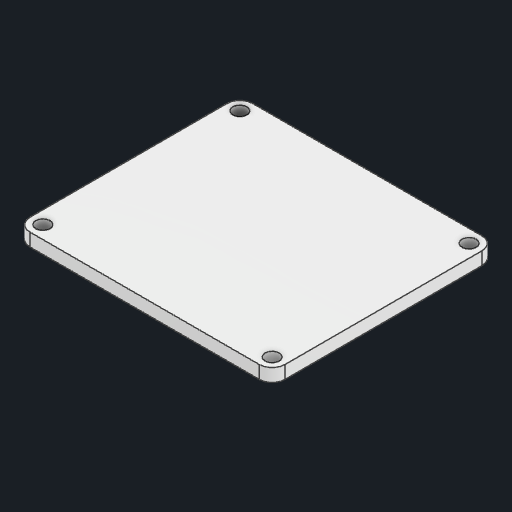
# Autodesk Inventor part: D1 COVER
Saved by Autodesk Inventor 2027.1 (Build 311270010, 270A)
## iProperties
Created: 2026-09-25
Part Number: D1 COVER
Material: ABS 플라스틱
Document SubType Name: Modeling
Designer: work
Density: 1.06 g/cm^3
Appearance: 매끄러움 - 흰색
Author: work
Autodesk Inventor part; units mm, degrees
ref_plane "YZ Plane" through (0, 0, 0) normal (1, 0, 0) x (0, 1, 0)
ref_plane "XZ Plane" through (0, 0, 0) normal (0, 1, 0) x (-1, 0, 0)
ref_plane "XY Plane" through (0, 0, 0) normal (0, 0, 1) x (1, 0, 0)
sketch "스케치1" plane through (0, 0, 0) normal (0, 1, 0) x (-1, 0, 0)
  line L0 (0, 0) -> (35.5, 0)
  line L1 (35.5, 0) -> (35.5, -26.5)
  line L2 (35.5, -26.5) -> (0, -26.5)
  line L3 (0, -26.5) -> (0, 0)
  line L4 (37.5, -28.5) -> (37.5, 2)
  line L5 (37.5, 2) -> (-2, 2) construction
  line L6 (-2, 2) -> (-2, -28.5)
  line L7 (-2, -28.5) -> (37.5, -28.5) construction
  circle A0 centre (35.5, 2) radius 1.1
  circle A1 centre (35.5, 2) radius 2
  circle A2 centre (0, 2) radius 1.1
  circle A3 centre (0, 2) radius 2
  line L8 (0, 4) -> (35.5, 4)
  line L9 (-2, -13.25) -> (37.5, -13.25) construction
  line L10 (0, -26.5) -> (35.5, -26.5)
  line L11 (35.5, -26.5) -> (35.5, 0)
  line L12 (0, 0) -> (0, -26.5)
  line L13 (37.5, 2) -> (37.5, -28.5)
  line L14 (37.5, -28.5) -> (-2, -28.5) construction
  line L15 (-2, -28.5) -> (-2, 2)
  circle A4 centre (35.5, -28.5) radius 1.1
  circle A5 centre (35.5, -28.5) radius 2
  circle A6 centre (0, -28.5) radius 1.1
  circle A7 centre (0, -28.5) radius 2
  line L16 (0, -30.5) -> (35.5, -30.5)
  line L17 (0, -8.25) -> (-2, -8.25)
  line L18 (-2, -8.25) -> (-2, -18.25)
  line L19 (-2, -18.25) -> (0, -18.25)
  line L20 (0, -18.25) -> (0, -8.25)
  line L21 (-2, -6.25) -> (-1, -6.25)
  line L22 (-1, -6.25) -> (-1, -20.25)
  line L23 (-1, -20.25) -> (-2, -20.25)
  line L24 (-2, -20.25) -> (-2, -6.25)
  point P0 (0, -13.25)
  point P1 (-2, -13.25)
  point P2 (-1, -13.25)
  dimension "d0" = 35.5
  dimension "d1" = 26.5
  dimension "d2" = 2
  dimension "d3" = 2.2
  dimension "d4" = 2.2
  dimension "d5" = 10
  dimension "d6" = 1
  dimension "d7" = 14
  constraints: 50 end point, 14 symmetric about line, 8 centre point, 8 parallel, 8 point on circle, 7 midpoint, 6 point on line, 4 coincident, 4 perpendicular, 3 horizontal, 2 tangent, 2 vertical alignment, 7 other
  measures "d0" distance of L1.end L2.end
  measures "d1" distance of L0.end L1.end
  measures "d2" distance between parallel lines of L1 L4
  measures "d3" diameter of A0
  measures "d4" diameter of A2
  measures "d5" distance of L17.end L18.end
  measures "d6" distance between parallel lines of L3 L22
  measures "d7" distance of L21.end L22.end
extrude "돌출1" add sketch "스케치1" along normal blind 2
extrude "돌출2" add sketch "스케치1" against normal blind 2 contours L0 L1 L2 L3
sketch "스케치2" plane through (0, -2, 0) normal (0, -1, 0) x (1, 0, 0)
  line L0 (-35.5, -26.5) -> (0, -26.5) projected
  line L1 (0, -26.5) -> (0, 0) projected
  line L2 (0, 0) -> (-35.5, 0) projected
  line L3 (-35.5, 0) -> (-35.5, -26.5) projected
  line L4 (-35, -0.5) -> (-0.5, -0.5)
  line L5 (-0.5, -0.5) -> (-0.5, -26)
  line L6 (-0.5, -26) -> (-35, -26)
  line L7 (-35, -26) -> (-35, -0.5)
  dimension "d12" = 0.5
  constraints: 8 end point, 3 other
  measures "d12" distance between parallel lines of L2 L4
extrude "돌출3" cut sketch "스케치2" against normal up to surface (2 mm away)
fillet "모깎기1" radius 2 4 edges at (-0.5, -1, -0.5) (-0.5, -1, -26) (-35, -1, -26) (-35, -1, -0.5)
sketch "스케치3" plane through (0, -2, 0) normal (0, -1, 0) x (1, 0, 0)
  line L0 (-0.5, -24) -> (-0.5, -2.5) projected
  line L1 (-0.5, -8.25) -> (-12.5, -8.25)
  line L2 (-12.5, -8.25) -> (-12.5, -18.25)
  line L3 (-12.5, -18.25) -> (-0.5, -18.25)
  line L4 (-0.5, -18.25) -> (-0.5, -8.25)
  point P0 (0, 0)
  point P1 (-0.5, -13.25)
  dimension "d16" = 10
  dimension "d17" = 12
  constraints: 8 end point, 2 midpoint, 2 parallel, 1 horizontal, 1 perpendicular, 1 point on line
  measures "d16" distance of L1.end L2.end
  measures "d17" distance of L2.end L3.end
extrude "돌출4" cut sketch "스케치3" against normal up to surface (2 mm away)
sketch "스케치4" plane through (0, -2, 0) normal (0, -1, 0) x (1, 0, 0)
  line L0 (-12.5, -8.25) -> (-0.5, -8.25) projected
  line L1 (-0.5, -8.25) -> (-0.5, -2.5) projected
  arc A0 (-0.5, -2.5) -> (-2.5, -0.5) centre (-2.5, -2.5) ccw projected
  line L2 (-2.5, -0.5) -> (-33, -0.5) projected
  arc A1 (-33, -0.5) -> (-35, -2.5) centre (-33, -2.5) ccw projected
  line L3 (-35, -2.5) -> (-35, -24) projected
  arc A2 (-35, -24) -> (-33, -26) centre (-33, -24) ccw projected
  line L4 (-33, -26) -> (-2.5, -26) projected
  arc A3 (-2.5, -26) -> (-0.5, -24) centre (-2.5, -24) ccw projected
  line L5 (-0.5, -24) -> (-0.5, -18.25) projected
  line L6 (-0.5, -18.25) -> (-12.5, -18.25) projected
  line L7 (-12.5, -18.25) -> (-12.5, -8.25) projected
  line L8 (-29, -2.5) -> (-33, -2.5) construction
  line L9 (-29, -0.5) -> (-33, -0.5)
  line L10 (-33, -4.5) -> (-29, -4.5)
  arc A4 (-29, -4.5) -> (-29, -0.5) centre (-29, -2.5) ccw
  arc A5 (-33, -0.5) -> (-33, -4.5) centre (-33, -2.5) ccw
  arc A6 (-33, -0.5) -> (-35, -2.5) centre (-33, -2.5) ccw projected
  line L11 (-35, -13.25) -> (-12.5, -13.25) construction
  line L12 (-29, -24) -> (-33, -24) construction
  line L13 (-33, -22) -> (-29, -22)
  arc A7 (-29, -26) -> (-29, -22) centre (-29, -24) ccw
  arc A8 (-33, -22) -> (-33, -26) centre (-33, -24) ccw
  point P0 (0, 0)
  point P1 (-31, -2.5)
  point P2 (-31, -24)
  dimension "d20" = 4
  constraints: 16 end point, 9 symmetric about line, 8 point on circle, 4 centre point, 4 tangent, 3 midpoint, 2 concentric, 1 horizontal, 1 parallel, 2 other
  measures "d20" distance of L8.start L8.end
extrude "돌출5" add sketch "스케치4" along normal blind 1.9 contours A4 L10 A5 A1 L2 | L4 A2 A8 L13 A7
fillet "모깎기2" radius 2 6 edges at (-31, -2, -4.5) (-34.4142, -2, -3.9142) (-27, -2, -2.5) (-27, -2, -24) (-34.4142, -2, -22.5858) (-31, -2, -22)
